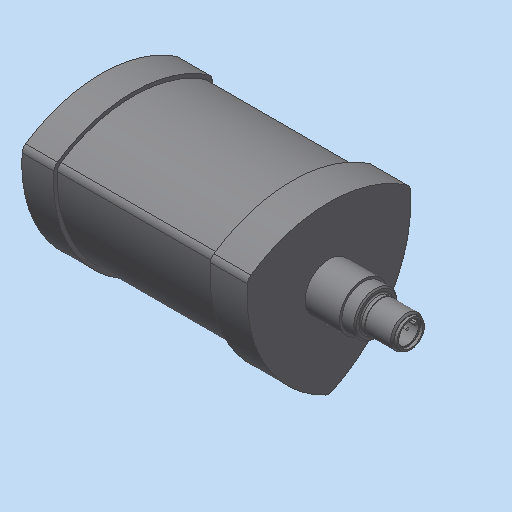
# Autodesk Inventor part: BNI007T__20200213
Saved by Autodesk Inventor 2023.3 (Build 273359000, 359)
## iProperties
Category: PARTsolutions
Company: BALLUFF
Created: 2020-01-29
Part Number: BNI007T__20200213
Material: Generisch
Catalog Web Link: www.cadenas.de
Description: =<RBPARTNOTITLE2>
Vendor: Balluff
Document SubType Name: Modeling
Designer: psadmin
Manufacturer: BALLUFF
Mass: 470 g
Surface Area: 239.678 cm^2
Volume: 223.441 cm^3
Density: 1 g/cm^3
Appearance: PSOLRGB-175-175-175
PSOL_IDENT_0: {$CADENAS_DATA\23d-libs\balluff\human_machine_interfaces\smartlight_led_signalsaulen\smartlight_led_
PSOL_IDENT_1: signalsaulen.prj},227 {VTYP=3D},{NB=BALLUFF BNI IOL-800-000-Z036},{LINA=BALLUFF BNI IOL-800-000-Z036
PSOL_IDENT_2: },{NN=Visual + acoustic signaling devices},{DATE=20.01.2020 13:43:25},{GEOMDATE=20.01.2020 13:43:19}
PSOL_IDENT_3: ,{VERSION=},{LINEID=1670},{WBVAR=},{WBNUMERIC=}  {NB=BALLUFF BNI IOL-800-000-Z036},{LINA=BALLUFF BNI
PSOL_IDENT_4: IOL-800-000-Z036},{KT=DUMMY},{VERF3=Available},{VERF2=no more available},{VERF1=Availability on req
PSOL_IDENT_5: uest},{VERF=Available},{ST=AK},{HIDDEN=0},{BC=BNI007T},{AB=BNI IOL-800-000-Z036},{AB1=BNI_IOL-800-00
PSOL_IDENT_6: 0-Z036},{PV=PV152270},{PX=50602_00},{IEC=IP65},{TECH=Tech. Detail},{LI=https://www.balluff.com/en/de
PSOL_IDENT_7: /productfinder/?geo=/variant/PV152270},{PWEB=yes},{ICON=50602_00.bmp},{RENDER=Q_20161021_Melde und A
PSOL_IDENT_8: nzeigegeraete_45°},{EDZ=BAL.BNI007T},{IODD=DRF_913660_05_000},{WEIGHT=470},{TRAFFIC=85318070},{BG=60
PSOL_IDENT_9: x 60 x 117 mm},{MOUNTDET=Schrauben M18},{SORT=IO-Link.},{SETPOS=Funktionsanzeige},{COLORPRE=gelb;we
PSOL_IDENT_10: iß;grün;blau;rot;orange;konfigurierbar},{SENST=Anzeigeleuchte},{ZUL=CE;cULus;WEEE},{CYCLETIME=5 ms}
NN: Visual + acoustic signaling devices
NB: BALLUFF BNI IOL-800-000-Z036
NBSYN: BALLUFF $AB.
LINA: BALLUFF BNI IOL-800-000-Z036
VERF: Available
BC: BNI007T
AB: BNI IOL-800-000-Z036
PX: 50602_00
IEC: IP65
TECH: Tech. Detail
ICON: 50602_00.bmp
EDZ: BAL.BNI007T
IODD: DRF_913660_05_000
WEIGHT: 470
TRAFFIC: 85318070
BG: 60 x 60 x 117 mm
MOUNTDET: Screws M18
SORT: IO-Link.
SETPOS: Function indicator
COLORPRE: yellow;white;green;blue;red;orange;configurable
SENST: Indicator light
ZUL: CE;cULus;WEEE
CYCLETIME: 5 ms
SUPPLIER: BALLUFF
ARTICLENO: BALLUFF BNI IOL-800-000-Z036
BOMINFO: BALLUFF BNI IOL-800-000-Z036
CREATOR: CADENAS GmbH
RBPARTNOTITLE1: signal pillar
AnP_Kategorie: 11
AnP_Material: =<Material>
RBDRAWINGMISSINGSPEC: --
RBGBREMARKSINDEX: E
RBPARTMADEOF: BNI007T
RBPARTNOTITLE2: Signalsaeule
RBMATERIAL: --
RBMATNO: =<Part Number>
AnP_Standard: 3
Title: BALLUFF BNI IOL-800-000-Z036
Author: Cadenas PARTsolutions
Keywords: =<RBPARTMADEOF>
Comments: =<RBSURFACE2>
Revision Number: 01
Autodesk Inventor part; units mm, degrees
ref_plane "YZ Plane" through (0, 0, 0) normal (1, 0, 0) x (0, 1, 0)
ref_plane "XZ Plane" through (0, 0, 0) normal (0, 1, 0) x (-1, 0, 0)
ref_plane "XY Plane" through (0, 0, 0) normal (0, 0, 1) x (1, 0, 0)
sketch "Sketch_1" plane through (12, 0, 0) normal (1, 0, 0) x (0, 0, -1)
  arc A0 (-17.2681, 27.1786) -> (-17.2681, -27.1786) centre (24.7, 0) ccw
  arc A1 (-17.2681, -27.1786) -> (-14.9033, -28.5439) centre (-14.7501, -25.5479) ccw
  arc A2 (-14.9033, -28.5439) -> (32.1714, -1.3654) centre (-12.35, 21.3908) ccw
  arc A3 (32.1714, -1.3654) -> (32.1714, 1.3654) centre (29.5001, 0) ccw
  arc A4 (32.1714, 1.3654) -> (-14.9033, 28.5439) centre (-12.35, -21.3908) ccw
  arc A5 (-14.9033, 28.5439) -> (-17.2681, 27.1786) centre (-14.7501, 25.5479) ccw
  constraints: 12 point on circle, 6 centre point
extrude "Extrusion1" add sketch "Sketch_1" along normal blind 60
sketch "Sketch_2" plane through (12, 0, 0) normal (1, 0, 0) x (0, 0, -1)
  arc A0 (-18.027, 28.572) -> (-18.027, -28.572) centre (24.7, 0) ccw
  arc A1 (-18.027, -28.572) -> (-15.7306, -29.8979) centre (-15.5333, -26.9044) ccw
  arc A2 (-15.7306, -29.8979) -> (33.7576, -1.3259) centre (-12.35, 21.3908) ccw
  arc A3 (33.7576, -1.3259) -> (33.7576, 1.3259) centre (31.0665, 0) ccw
  arc A4 (33.7576, 1.3259) -> (-15.7306, 29.8979) centre (-12.35, -21.3908) ccw
  arc A5 (-15.7306, 29.8979) -> (-18.027, 28.572) centre (-15.5333, 26.9044) ccw
  constraints: 12 point on circle, 6 centre point
extrude "Extrusion2" add sketch "Sketch_2" against normal blind 12
sketch "Sketch_6" plane through (72, 0, 0) normal (1, 0, 0) x (0, 0, -1)
  arc A0 (-18.5174, 29.4702) -> (-18.5174, -29.4702) centre (24.7, 0) ccw
  arc A1 (-18.5174, -29.4702) -> (-16.2632, -30.7716) centre (-16.0388, -27.78) ccw
  arc A2 (-16.2632, -30.7716) -> (34.7806, -1.3014) centre (-12.35, 21.3908) ccw
  arc A3 (34.7806, -1.3014) -> (34.7806, 1.3014) centre (32.0776, 0) ccw
  arc A4 (34.7806, 1.3014) -> (-16.2632, 30.7716) centre (-12.35, -21.3908) ccw
  arc A5 (-16.2632, 30.7716) -> (-18.5174, 29.4702) centre (-16.0388, 27.78) ccw
  constraints: 12 point on circle, 6 centre point
extrude "Extrusion3" add sketch "Sketch_6" along normal blind 14
sketch "Sketch_7" plane through (0, 0, 0) normal (0, 0, 1) x (1, 0, 0)
  line L0 (105.7, 0) -> (86, 0)
  line L1 (86, 0) -> (86, 9)
  line L2 (86, 9) -> (99, 9)
  line L3 (99, 9) -> (99, 8.15)
  line L4 (99, 8.15) -> (103.5, 8.15)
  line L5 (103.5, 8.15) -> (104, 7.65)
  line L6 (104, 7.65) -> (104, 6.6913)
  arc A0 (104, 6.6913) -> (104.4913, 6.1914) centre (104.5, 6.6913) ccw
  line L7 (104.4913, 6.1914) -> (105.7, 6.1703)
  line L8 (105.7, 6.1703) -> (105.7, 0)
  line L9 (105.7, 0) -> (86, 0)
  constraints: 20 end point, 2 point on circle, 1 centre point
revolve "Revolution1" add sketch "Sketch_7" angle 360 about axis through (105.7, 0, 0) along (1, 0, 0)
sketch "Sketch_8" plane through (0, 0, 0) normal (0, 0, 1) x (1, 0, 0)
  line L0 (116.9, 0) -> (105.7, 0)
  line L1 (105.7, 0) -> (105.7, 6)
  line L2 (105.7, 6) -> (115.2865, 6)
  line L3 (115.2865, 6) -> (115.9, 5.3865)
  line L4 (115.9, 5.3865) -> (115.9, 5.2)
  line L5 (115.9, 5.2) -> (116.9, 5.2)
  line L6 (116.9, 5.2) -> (116.9, 0)
  line L7 (116.9, 0) -> (105.7, 0)
  constraints: 16 end point
revolve "Revolution2" add sketch "Sketch_8" angle 360 about axis through (116.9, 0, 0) along (1, 0, 0)
sketch "Sketch_9" plane through (0, 0, 0) normal (0, 0, 1) x (1, 0, 0)
  line L0 (116.9, 0) -> (106.9, 0)
  line L1 (106.9, 0) -> (106.9, 4.15)
  line L2 (106.9, 4.15) -> (115.7, 4.15)
  arc A0 (115.7, 4.15) -> (115.9, 4.35) centre (115.7, 4.35) ccw
  line L3 (115.9, 4.35) -> (115.9, 4.65)
  line L4 (115.9, 4.65) -> (116.9, 4.65)
  line L5 (116.9, 4.65) -> (116.9, 0)
  line L6 (116.9, 0) -> (106.9, 0)
  constraints: 14 end point, 2 point on circle, 1 centre point
revolve "Revolution3" cut sketch "Sketch_9" angle 360 about axis through (116.9, 0, 0) along (1, 0, 0)
sketch "Sketch_10" plane through (106.9, 0, 0) normal (1, 0, 0) x (0, 0, -1)
  arc A0 (-3.6029, 0.5186) -> (-2.8565, -2.2562) centre (0, 0) ccw
  arc A1 (-2.8565, -2.2562) -> (-2.4996, -2.1374) centre (-2.6995, -2.1322) ccw
  arc A2 (-0.5949, -3.2346) -> (-2.4996, -2.1374) centre (-1.25, -2.17) ccw
  arc A3 (-0.5949, -3.2346) -> (-0.5186, -3.6029) centre (-0.4901, -3.4049) ccw
  arc A4 (-0.5186, -3.6029) -> (2.2562, -2.8565) centre (0, 0) ccw
  arc A5 (2.2562, -2.8565) -> (2.1374, -2.4996) centre (2.1322, -2.6995) ccw
  arc A6 (3.2346, -0.5949) -> (2.1374, -2.4996) centre (2.17, -1.25) ccw
  arc A7 (3.2346, -0.5949) -> (3.6029, -0.5186) centre (3.4049, -0.4901) ccw
  arc A8 (3.6029, -0.5186) -> (2.8565, 2.2562) centre (0, 0) ccw
  arc A9 (2.8565, 2.2562) -> (2.4996, 2.1374) centre (2.6995, 2.1322) ccw
  arc A10 (0.5949, 3.2346) -> (2.4996, 2.1374) centre (1.25, 2.17) ccw
  arc A11 (0.5949, 3.2346) -> (0.5186, 3.6029) centre (0.4901, 3.4049) ccw
  arc A12 (0.5186, 3.6029) -> (-2.2562, 2.8565) centre (0, 0) ccw
  arc A13 (-2.2562, 2.8565) -> (-2.1374, 2.4996) centre (-2.1322, 2.6995) ccw
  arc A14 (-3.2346, 0.5949) -> (-2.1374, 2.4996) centre (-2.17, 1.25) ccw
  arc A15 (-3.2346, 0.5949) -> (-3.6029, 0.5186) centre (-3.4049, 0.4901) ccw
  constraints: 32 point on circle, 16 centre point
extrude "Extrusion4" cut sketch "Sketch_10" against normal blind 1
sketch "Sketch_11" plane through (0, 0, 2.17) normal (0, 0, 1) x (1, 0, 0)
  line L0 (113.9, 1.25) -> (106.9, 1.25)
  line L1 (106.9, 1.25) -> (106.9, 1.75)
  line L2 (106.9, 1.75) -> (113.4, 1.75)
  arc A0 (113.9, 1.25) -> (113.4, 1.75) centre (113.4, 1.25) ccw
  line L3 (113.9, 1.25) -> (106.9, 1.25)
  constraints: 8 end point, 2 point on circle, 1 centre point
revolve "Revolution4" add sketch "Sketch_11" angle 360 about axis through (113.9, 1.25, 2.17) along (1, 0, 0)
pattern_linear "Rectangular Pattern1" count 2 spacing 3.5416 along (0, 0.2598, -0.9657) count 2 spacing 3.5416 along (0, -0.9657, -0.2598) of "Revolution4"
sketch "Sketch_13" plane through (106.9, 0, 0) normal (1, 0, 0) x (0, 0, -1)
  line L0 (-1.6424, 3.8112) -> (-1.4725, 3.1772)
  arc A0 (-1.4725, 3.1772) -> (-0.8601, 2.8236) centre (-0.9895, 3.3066) ccw
  line L1 (-0.8601, 2.8236) -> (-0.6669, 2.8754)
  arc A1 (-0.6669, 2.8754) -> (-0.3134, 3.4877) centre (-0.7963, 3.3583) ccw
  line L2 (-0.3134, 3.4877) -> (-0.4833, 4.1218)
  arc A2 (-0.4833, 4.1218) -> (-1.6424, 3.8112) centre (0, 0) ccw
  constraints: 6 end point, 6 point on circle, 3 centre point
extrude "Extrusion5" add sketch "Sketch_13" along normal blind 8.5
body "Solid1"
